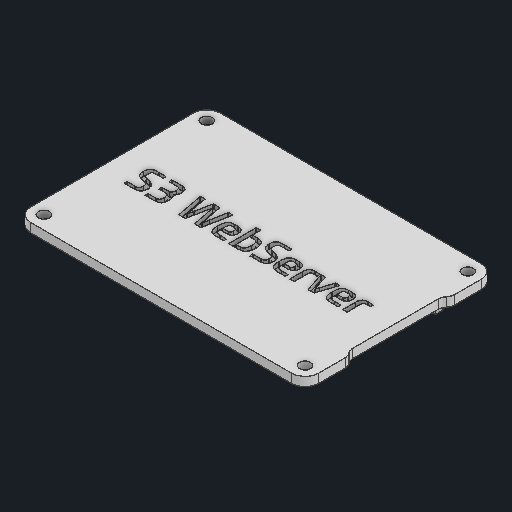
# Autodesk Inventor part: COVER
Saved by Autodesk Inventor 2027 (Build 310192000, 192)
## iProperties
Created: 2026-09-25
Part Number: COVER
Material: 일반
Document SubType Name: Modeling
Designer: work
Density: 1 g/cm^3
Appearance: 기본값
Author: work
Autodesk Inventor part; units mm, degrees
ref_plane "YZ Plane" through (0, 0, 0) normal (1, 0, 0) x (0, 1, 0)
ref_plane "XZ Plane" through (0, 0, 0) normal (0, 1, 0) x (-1, 0, 0)
ref_plane "XY Plane" through (0, 0, 0) normal (0, 0, 1) x (1, 0, 0)
sketch "스케치1" plane through (0, 0, 0) normal (0, 1, 0) x (-1, 0, 0)
  line L0 (0, 0) -> (58.5, 0)
  line L1 (58.5, 0) -> (58.5, -28.5)
  line L2 (58.5, -28.5) -> (0, -28.5)
  line L3 (0, -28.5) -> (0, 0)
  line L4 (-2, -30.5) -> (60.5, -30.5)
  line L5 (60.5, -30.5) -> (60.5, 2)
  line L6 (60.5, 2) -> (-2, 2)
  line L7 (-2, 2) -> (-2, -30.5)
  line L8 (0, -3.75) -> (-2, -3.75)
  line L9 (-2, -3.75) -> (-2, -24.75)
  line L10 (-2, -24.75) -> (0, -24.75)
  line L11 (0, -24.75) -> (0, -3.75)
  line L12 (58.5, -5.25) -> (60.5, -5.25)
  line L13 (60.5, -5.25) -> (60.5, -23.25)
  line L14 (60.5, -23.25) -> (58.5, -23.25)
  line L15 (58.5, -23.25) -> (58.5, -5.25)
  circle A0 centre (60.5, 0) radius 1.1
  line L16 (58.5, -14.25) -> (60.5, -14.25) construction
  circle A1 centre (60.5, 0) radius 2
  circle A2 centre (60.5, -28.5) radius 1.1
  circle A3 centre (60.5, -28.5) radius 2
  circle A4 centre (-2, 0) radius 1.1
  circle A5 centre (-2, 0) radius 2
  circle A6 centre (-2, -28.5) radius 1.1
  circle A7 centre (-2, -28.5) radius 2
  line L17 (58.5, 0) -> (48.5, 0)
  line L18 (48.5, 0) -> (48.5, -3)
  line L19 (48.5, -3) -> (58.5, -3)
  line L20 (58.5, -3) -> (58.5, 0)
  line L21 (48.5, -28.5) -> (48.5, -25.5)
  line L22 (48.5, -25.5) -> (58.5, -25.5)
  line L23 (29.25, -30.5) -> (29.25, 2) construction
  line L24 (10, 0) -> (10, -3)
  line L25 (10, -3) -> (0, -3)
  line L26 (10, -25.5) -> (0, -25.5)
  line L27 (10, -28.5) -> (10, -25.5)
  point P0 (0, -14.25)
  point P1 (-2, -14.25)
  point P2 (59.5, -23.25)
  point P3 (59.5, -5.25)
  point P4 (60.5, -2)
  point P5 (-2, -2)
  point P6 (-2, -26.5)
  point P7 (-2, -30.5)
  point P8 (60.5, -30.5)
  point P9 (60.5, -26.5)
  point P10 (10, -28.5)
  point P11 (0, -25.5)
  point P12 (48.5, -28.5)
  point P13 (48.5, 0)
  dimension "d0" = 58.5
  dimension "d1" = 28.5
  dimension "d2" = 2
  dimension "d3" = 21
  dimension "d4" = 18
  dimension "d5" = 2.2
  dimension "d6" = 2.2
  dimension "d7" = 10
  dimension "d8" = 3
  constraints: 56 end point, 13 symmetric about line, 12 midpoint, 10 parallel, 6 centre point, 5 horizontal, 5 perpendicular, 4 coincident, 2 horizontal alignment, 2 point on line, 13 other
  measures "d0" distance of L1.end L2.end
  measures "d1" distance of L0.end L1.end
  measures "d2" distance between parallel lines of L2 L4
  measures "d3" distance of L8.end L9.end
  measures "d4" distance of point (59.5, -23.25) point (59.5, -5.25)
  measures "d5" diameter of A0
  measures "d6" diameter of A4
  measures "d7" distance of L19.end L18.end
  measures "d8" distance of L18.end L17.end
extrude "돌출1" add sketch "스케치1" along normal blind 2 contours A5 L6 A1 L0 | L0 L24 L25 L3 | A5 L7 A4 | L3 L8 L7 A5 | L0 L18 L19 L1 L22 L21 L2 L27 L26 L3 L25 L24 | L0 L1 L19 L18 | L3 L10 L7 L8 | L5 A0 A1 | A4 L7 | A1 L5 L12 L1 | L3 A7 L7 L10 | L5 A0 | L26 L27 L2 L3 | A7 L7 A6 | L12 L5 L14 L1 | L2 A3 L4 A7 | A6 L7 | L14 L5 A3 L1 | A3 L5 A2 | L1 L2 L21 L22 | A2 L5 picked at (-0.3259, -0.2299) picked at (60.3517, -1.6833) picked at (-1.7714, 0.2867) picked at (60.136, -0.0442) picked at (-0.419, -27.9033) picked at (-1.5307, -28.8138) picked at (60.3517, -26.8167) picked at (60.136, -28.5442)
extrude "돌출2" add sketch "스케치1" against normal blind 3 contours L0 L24 L25 L3 | L0 L1 L19 L18 | L26 L27 L2 L3 | L1 L2 L21 L22
sketch "스케치2" plane through (0, -3, 0) normal (0, -1, 0) x (1, 0, 0)
  line L0 (0, -25.5) -> (0, -28.5) projected
  line L1 (0, -28.5) -> (-10, -28.5) projected
  line L2 (-10, -28.5) -> (-10, -25.5) projected
  line L3 (-10, -25.5) -> (0, -25.5) projected
  line L4 (-58.5, -28.5) -> (-58.5, -25.5) projected
  line L5 (-58.5, -25.5) -> (-48.5, -25.5) projected
  line L6 (-48.5, -25.5) -> (-48.5, -28.5) projected
  line L7 (-48.5, -28.5) -> (-58.5, -28.5) projected
  line L8 (0, 0) -> (0, -3) projected
  line L9 (0, -3) -> (-10, -3) projected
  line L10 (-10, -3) -> (-10, 0) projected
  line L11 (-10, 0) -> (0, 0) projected
  line L12 (-58.5, 0) -> (-48.5, 0) projected
  line L13 (-48.5, 0) -> (-48.5, -3) projected
  line L14 (-48.5, -3) -> (-58.5, -3) projected
  line L15 (-58.5, -3) -> (-58.5, 0) projected
  line L16 (-60.5, 2) -> (2, 2) projected
  line L17 (-60.5, -30.5) -> (-60.5, 2) projected
  line L18 (2, -30.5) -> (-60.5, -30.5) projected
  line L19 (2, 2) -> (2, -30.5) projected
  line L20 (-0.3, -28.2) -> (-58.3, -28.2)
  line L21 (-58.3, -28.2) -> (-58.3, -0.3)
  line L22 (-58.3, -0.3) -> (-0.3, -0.3)
  line L23 (-0.3, -0.3) -> (-0.3, -28.2)
  line L24 (-0.3, -28.2) -> (-58.3, -0.3) construction
  line L25 (-58.3, -28.2) -> (-0.3, -0.3) construction
  point P0 (-29.3, -14.25)
  point P1 (-0.3, -25.5)
  point P2 (-10, -28.2)
  point P3 (-48.5, -28.2)
  point P4 (-58.3, -25.5)
  point P5 (-58.3, -3)
  point P6 (-48.5, -0.3)
  point P7 (-10, -0.3)
  point P8 (-0.3, -3)
  dimension "d13" = 0.3
  dimension "d14" = 0.2
  dimension "d15" = 0.3
  dimension "d16" = 0.3
  constraints: 12 end point, 2 midpoint, 2 parallel, 1 horizontal, 1 perpendicular
  measures "d13" distance between parallel lines of L12 L22
  measures "d14" distance between parallel lines of L15 L21
  measures "d15" distance between parallel lines of L1 L20
  measures "d16" distance between parallel lines of L0 L23
extrude "돌출3" cut sketch "스케치2" against normal up to surface (3 mm away) contours L0 L1 L2 L20 L23 L3 | L23 L22 L10 L11 L8 L9 | L6 L7 L4 L5 L21 L20 | L22 L21 L14 L15 L12 L13
fillet "모깎기1" radius 1 4 edges at (-0.3, -1.5, -28.2) (-0.3, -1.5, -0.3) (-58.3, -1.5, -28.2) (-58.3, -1.5, -0.3)
extrude "돌출4" add sketch "스케치1" against normal blind 2 contours L12 L5 L14 L1
sketch "스케치3" plane through (0, -2, 0) normal (0, -1, 0) x (1, 0, 0)
  line L0 (-60.5, -30.5) -> (-60.5, 2) projected
  line L1 (-60.5, -14) -> (-58.5, -14.25) construction
  line L2 (-58.5, -23.25) -> (-58.5, -5.25) projected
  line L3 (-60.5, -22.95) -> (-58.5, -22.95)
  line L4 (-60.5, -23.25) -> (-58.5, -23.25) projected
  line L5 (-58.2969, -5.3254) -> (-56.3585, -5.8177)
  line L6 (-58.2231, -5.0346) -> (-58.5, -5.25)
  point P0 (0, 0)
  point P1 (-60, -26)
  point P2 (-60, -2)
  point P3 (-59.5, -22.95)
  point P4 (-60, -5)
  point P5 (-60, -5.3)
  point P6 (-58, -5.3)
  point P7 (-58.5, -22.95)
  point P8 (-60.5, -22.95)
  point P9 (-60.5, 2)
  dimension "d22" = 0.3
  constraints: 8 end point, 3 symmetric about line, 2 midpoint, 1 horizontal, 2 other
  measures "d22" distance from line of L4 point (-59.5, -22.95)
extrude "돌출5" cut sketch "스케치3" against normal blind 2
sketch "스케치4" plane through (0, 2, 0) normal (0, 1, 0) x (1, 0, 0)
  line L0 (-60.5, -2) -> (2, -2) projected
  line L1 (-14, -2) -> (-14, 30.5) construction
  line L2 (2, 30.5) -> (-60.5, 30.5) projected
  line L3 (2, -2) -> (2, 30.5) projected
  circle A0 centre (-14, 11.5) radius 0.5
  point P0 (0, 0)
  point P1 (2, 30)
  point P2 (-60, 30)
  point P3 (2, 2)
  point P4 (2, 26)
  dimension "d25" = 16
  dimension "d26" = 1
  dimension "d27" = 19
  constraints: 2 end point, 2 point on line, 1 centre point, 1 vertical, 2 other
  measures "d25" distance between parallel lines of L3 L1
  measures "d26" diameter of A0
  measures "d27" distance of L1.end A0.centre
sketch "스케치7" plane through (0, 0, 0) normal (0, -1, 0) x (1, 0, 0)
  line L0 (-60.5, -30.5) -> (-60.5, -22.95) projected
  line L1 (2, -30.5) -> (-60.5, -30.5) projected
  line L2 (2, 2) -> (2, -30.5) projected
  line L3 (-60.5, 2) -> (2, 2) projected
  line L4 (-60.5, -5.25) -> (-60.5, 2) projected
  line L5 (-58.5, -5.25) -> (-58.5, -22.95) projected
  line L6 (-60.5, -22.95) -> (-58.5, -22.95) projected
  line L7 (-10, -28.2) -> (-10, -25.5) projected
  line L8 (-10, -25.5) -> (-0.3, -25.5) projected
  line L9 (-0.3, -25.5) -> (-0.3, -27.2) projected
  arc A0 (-1.3, -28.2) -> (-0.3, -27.2) centre (-1.3, -27.2) ccw projected
  line L10 (-1.3, -28.2) -> (-10, -28.2) projected
  line L11 (-58.3, -25.5) -> (-48.5, -25.5) projected
  line L12 (-48.5, -25.5) -> (-48.5, -28.2) projected
  line L13 (-48.5, -28.2) -> (-57.3, -28.2) projected
  arc A1 (-58.3, -27.2) -> (-57.3, -28.2) centre (-57.3, -27.2) ccw projected
  line L14 (-58.3, -27.2) -> (-58.3, -25.5) projected
  line L15 (-0.3, -3) -> (-10, -3) projected
  line L16 (-10, -3) -> (-10, -0.3) projected
  line L17 (-10, -0.3) -> (-1.3, -0.3) projected
  arc A2 (-0.3, -1.3) -> (-1.3, -0.3) centre (-1.3, -1.3) ccw projected
  line L18 (-0.3, -1.3) -> (-0.3, -3) projected
  line L19 (-48.5, -0.3) -> (-48.5, -3) projected
  line L20 (-48.5, -3) -> (-58.3, -3) projected
  line L21 (-58.3, -3) -> (-58.3, -1.3) projected
  arc A3 (-57.3, -0.3) -> (-58.3, -1.3) centre (-57.3, -1.3) ccw projected
  line L22 (-57.3, -0.3) -> (-48.5, -0.3) projected
  line L23 (-10, -0.3) -> (-48.5, -0.3)
  line L24 (-48.5, -0.3) -> (-48.5, -3)
  line L25 (-48.5, -3) -> (-10, -3)
  line L26 (-10, -3) -> (-10, -0.3)
  line L27 (-10, -25.5) -> (-48.5, -25.5)
  line L28 (-48.5, -25.5) -> (-48.5, -28.2)
  line L29 (-48.5, -28.2) -> (-10, -28.2)
  line L30 (-10, -28.2) -> (-10, -25.5)
  line L31 (-60.5, -5.25) -> (-58.5, -5.25) projected
  point P0 (0, 0)
  constraints: 16 end point, 4 parallel, 2 horizontal, 2 perpendicular
extrude "돌출7" add sketch "스케치7" along normal up to surface (3 mm away) contours L29 L12 L27 L7 | L25 L19 L23 L16
fillet "모깎기4" radius 2 2 edges at (-29.3, 0, -3) (-29.3, 0, -25.5)
sketch "스케치8" plane through (0, 0, 0) normal (0, -1, 0) x (1, 0, 0)
  line L0 (2, 2) -> (2, -30.5) projected
  line L1 (2, -14.25) -> (-60.5, -14.25) construction
  line L2 (-60.5, -30.5) -> (-60.5, 2) projected
  circle A0 centre (0, -32.5) radius 1.25
  line L3 (2, -30.5) -> (-60.5, -30.5) projected
  circle A1 centre (-58.5, -32.5) radius 1.25
  line L4 (0, -32.5) -> (-58.5, -32.5) construction
  line L5 (0, -30.5) -> (-58.5, -30.5)
  line L6 (-58.5, -34.5) -> (0, -34.5)
  arc A2 (0, -34.5) -> (0, -30.5) centre (0, -32.5) ccw
  arc A3 (-58.5, -30.5) -> (-58.5, -34.5) centre (-58.5, -32.5) ccw
  line L7 (-60.5, -30.5) -> (-60.5, -32.5)
  line L8 (2, -32.5) -> (2, -30.5)
  circle A4 centre (0, 4) radius 1.25
  circle A5 centre (-58.5, 4) radius 1.25
  line L9 (0, 4) -> (-58.5, 4) construction
  line L10 (-58.5, 6) -> (0, 6)
  arc A6 (0, 2) -> (0, 6) centre (0, 4) ccw
  arc A7 (-58.5, 6) -> (-58.5, 2) centre (-58.5, 4) ccw
  line L11 (-60.5, 2) -> (-60.5, 4)
  line L12 (2, 4) -> (2, 2)
  point P0 (0, 0)
  point P1 (-29.25, -32.5)
  point P2 (-58.5, -30.5)
  point P3 (0, -30.5)
  dimension "d46" = 2.5
  dimension "d47" = 2
  dimension "d48" = 2
  dimension "d49" = 2.5
  dimension "d50" = 2
  dimension "d51" = 2
  constraints: 24 end point, 10 point on circle, 9 symmetric about line, 8 centre point, 5 tangent, 3 midpoint, 2 coincident, 1 parallel, 4 other
  measures "d46" diameter of A0
  measures "d47" distance from line of L3 L4.start
  measures "d48" horizontal distance of L0.end L4.start
  measures "d49" diameter of A1
  measures "d50" horizontal distance of L2.start A1.centre
  measures "d51" horizontal distance of A1.centre L2.start
extrude "돌출8" add sketch "스케치8" against normal up to surface (2 mm away)
fillet "모깎기5" radius 2 1 edges at (-58.5, 0, -14.1)
sketch "스케치9" plane through (0, 2, 0) normal (0, 1, 0) x (1, 0, 0)
  circle A0 centre (-58.5, -4) radius 0.95
  circle A1 centre (0, -4) radius 0.95
  line L0 (-58.5, 0) -> (-58.5, 5.25)
  line L1 (-58.5, 5.25) -> (-61.5, 5.25)
  line L2 (-61.5, 5.25) -> (-61.5, -4)
  arc A2 (-61.5, -4) -> (-58.5, -7) centre (-58.5, -4) ccw
  line L3 (-58.5, -7) -> (0, -7)
  arc A3 (0, -7) -> (3, -4) centre (0, -4) ccw
  line L4 (3, -4) -> (3, 3.75)
  line L5 (3, 3.75) -> (0, 3.75)
  line L6 (0, 3.75) -> (0, 0)
  line L7 (0, 0) -> (-58.5, 0)
  circle A4 centre (0, 32.5) radius 0.95
  circle A5 centre (-58.5, 32.5) radius 0.95
  line L8 (-61.5, 23.25) -> (-58.5, 23.25)
  line L9 (-58.5, 23.25) -> (-58.5, 28.5)
  line L10 (-58.5, 28.5) -> (0, 28.5)
  line L11 (0, 28.5) -> (0, 24.75)
  line L12 (0, 24.75) -> (3, 24.75)
  line L13 (3, 24.75) -> (3, 32.5)
  arc A6 (3, 32.5) -> (0, 35.5) centre (0, 32.5) ccw
  line L14 (0, 35.5) -> (-58.5, 35.5)
  arc A7 (-58.5, 35.5) -> (-61.5, 32.5) centre (-58.5, 32.5) ccw
  line L15 (-61.5, 32.5) -> (-61.5, 23.25)
  line L16 (2, 24.75) -> (2, 3.75) construction
  line L17 (2, 3.75) -> (3, 3.75) construction
  line L18 (3, 3.75) -> (3, -4) construction
  arc A8 (0, -7) -> (3, -4) centre (0, -4) ccw construction
  line L19 (0, -7) -> (-58.5, -7) construction
  arc A9 (-61.5, -4) -> (-58.5, -7) centre (-58.5, -4) ccw construction
  line L20 (-61.5, -4) -> (-61.5, 5.25) construction
  line L21 (-61.5, 5.25) -> (-60.5, 5.25) construction
  line L22 (-60.5, 23.25) -> (-60.5, 5.25) construction
  line L23 (-60.5, 23.25) -> (-61.5, 23.25) construction
  line L24 (-61.5, 23.25) -> (-61.5, 32.5) construction
  arc A10 (-58.5, 35.5) -> (-61.5, 32.5) centre (-58.5, 32.5) ccw construction
  line L25 (-58.5, 35.5) -> (0, 35.5) construction
  arc A11 (3, 32.5) -> (0, 35.5) centre (0, 32.5) ccw construction
  line L26 (3, 32.5) -> (3, 24.75) construction
  line L27 (3, 24.75) -> (2, 24.75) construction
  circle A12 centre (-58.5, 32.5) radius 1.25 projected
  circle A13 centre (0, 32.5) radius 1.25 projected
  circle A14 centre (-58.5, -4) radius 1.25 projected
  circle A15 centre (0, -4) radius 1.25 projected
  line L28 (2, 32.5) -> (2, -4) projected
  arc A16 (2, 32.5) -> (0, 34.5) centre (0, 32.5) ccw projected
  line L29 (-58.5, 34.5) -> (0, 34.5) projected
  arc A17 (-58.5, 34.5) -> (-60.5, 32.5) centre (-58.5, 32.5) ccw projected
  line L30 (-60.5, -4) -> (-60.5, 32.5) projected
  arc A18 (-60.5, -4) -> (-58.5, -6) centre (-58.5, -4) ccw projected
  line L31 (0, -6) -> (-58.5, -6) projected
  arc A19 (0, -6) -> (2, -4) centre (0, -4) ccw projected
  line L32 (-61.5, 5.25) -> (-61.5, 23.25)
  line L33 (3, 24.75) -> (3, 3.75)
  point P0 (0, 0)
  point P1 (2, 3.75)
  point P2 (2, 24.75)
  constraints: 60 end point, 16 point on circle, 12 centre point, 1 parallel, 1 vertical
extrude "돌출9" add sketch "스케치9" against normal up to surface (2 mm away) contours L7 L6 L5 L28 A19 L31 A18 L30 L1 L0 | L0 L1 L30 L8 L9 L10 L11 L12 L28 L5 L6 L7 | L30 A18 L31 A19 L28 L5 L4 A3 L3 A2 L2 L1 | L1 L32 L8 L30 | L30 A17 L29 A16 L28 L12 L11 L10 L9 L8 | L8 L15 A7 L14 A6 L13 L12 L28 A16 L29 A17 L30
fillet "모깎기6" radius 2 4 edges at (2, 1, -3.75) (2, 1, -24.75) (3, 1, -24.75) (3, 1, -3.75)
sketch "스케치11" plane through (0, 2, 0) normal (0, 1, 0) x (1, 0, 0)
  line L0 (-56.1428, 17.2765) -> (30.9007, 17.2765) construction
  line L1 (30.9007, 17.2765) -> (30.9007, -13.3116) construction
  line L2 (30.9007, -13.3116) -> (-56.1428, -13.3116) construction
  line L3 (-56.1428, -13.3116) -> (-56.1428, 17.2765) construction
  spline S0 degree 2 poles (-53.8297, 16.4272) (-54.1294, 16.4272) (-54.4991, 16.3523) (-54.699, 16.1575) (-54.7689, 15.8127) (-54.7689, 15.543) knots 0 0 0 1 2 3 4 4 4
  spline S1 degree 2 poles (-54.7689, 15.543) (-54.7689, 15.3381) (-54.7389, 15.0484) (-54.629, 14.8386) (-54.4142, 14.6937) (-54.2294, 14.6437) knots 0 0 0 1 2 3 4 4 4
  line L4 (-54.2294, 14.6437) -> (-53.0603, 14.324)
  spline S2 degree 2 poles (-53.0603, 14.324) (-52.7206, 14.2291) (-52.266, 13.9393) (-51.9862, 13.5297) (-51.8713, 13.0051) (-51.8713, 12.6704) knots 0 0 0 1 2 3 4 4 4
  spline S3 degree 2 poles (-51.8713, 12.6704) (-51.8713, 12.1658) (-52.1011, 11.5413) (-52.5907, 11.2066) (-53.3451, 11.0917) (-53.8747, 11.0917) knots 0 0 0 1 2 3 4 4 4
  line L5 (-53.8747, 11.0917) -> (-55.5982, 11.0917)
  spline S4 degree 2 poles (-55.5982, 11.0917) (-55.6831, 11.0917) (-55.6831, 11.1666) knots 0 0 0 1 1 1
  line L6 (-55.6831, 11.1666) -> (-55.6831, 11.6812)
  spline S5 degree 2 poles (-55.6831, 11.6812) (-55.6831, 11.7311) (-55.6332, 11.7561) (-55.5982, 11.7561) knots 0 0 0 1 2 2 2
  line L7 (-55.5982, 11.7561) -> (-53.8597, 11.7561)
  spline S6 degree 2 poles (-53.8597, 11.7561) (-53.5399, 11.7561) (-53.1603, 11.866) (-52.9754, 12.0859) (-52.9205, 12.4356) (-52.9205, 12.6804) knots 0 0 0 1 2 3 4 4 4
  spline S7 degree 2 poles (-52.9205, 12.6804) (-52.9205, 12.8952) (-52.9504, 13.1899) (-53.0603, 13.3848) (-53.2652, 13.5147) (-53.445, 13.5596) knots 0 0 0 1 2 3 4 4 4
  line L8 (-53.445, 13.5596) -> (-54.629, 13.8943)
  spline S8 degree 2 poles (-54.629, 13.8943) (-55.2885, 14.0792) (-55.803, 14.8935) (-55.803, 15.563) knots 0 0 0 1 2 2 2
  spline S9 degree 2 poles (-55.803, 15.563) (-55.803, 16.0725) (-55.5732, 16.682) (-55.0936, 16.9968) (-54.3692, 17.0917) (-53.8647, 17.0917) knots 0 0 0 1 2 3 4 4 4
  line L9 (-53.8647, 17.0917) -> (-52.306, 17.0917)
  spline S10 degree 2 poles (-52.306, 17.0917) (-52.221, 17.0917) (-52.221, 17.0167) knots 0 0 0 1 1 1
  line L10 (-52.221, 17.0167) -> (-52.221, 16.5022)
  spline S11 degree 2 poles (-52.221, 16.5022) (-52.221, 16.4522) (-52.271, 16.4272) (-52.306, 16.4272) knots 0 0 0 1 2 2 2
  line L11 (-52.306, 16.4272) -> (-53.8297, 16.4272)
  spline S12 degree 2 poles (-50.9271, 11.0917) (-51.012, 11.0917) (-51.012, 11.1666) knots 0 0 0 1 1 1
  line L12 (-51.012, 11.1666) -> (-51.012, 11.6812)
  spline S13 degree 2 poles (-51.012, 11.6812) (-51.012, 11.7311) (-50.9621, 11.7561) (-50.9271, 11.7561) knots 0 0 0 1 2 2 2
  line L13 (-50.9271, 11.7561) -> (-49.1336, 11.7561)
  spline S14 degree 2 poles (-49.1336, 11.7561) (-48.9438, 11.7561) (-48.644, 11.8411) (-48.4492, 12.0709) (-48.3493, 12.4805) (-48.3493, 12.8053) knots 0 0 0 1 2 3 4 4 4
  spline S15 degree 2 poles (-48.3493, 12.8053) (-48.3493, 13.13) (-48.4492, 13.5446) (-48.644, 13.7744) (-48.9438, 13.8694) (-49.1386, 13.8694) knots 0 0 0 1 2 3 4 4 4
  line L14 (-49.1386, 13.8694) -> (-50.6274, 13.8694)
  spline S16 degree 2 poles (-50.6274, 13.8694) (-50.6623, 13.8694) (-50.7123, 13.8943) (-50.7123, 13.9443) knots 0 0 0 1 2 2 2
  line L15 (-50.7123, 13.9443) -> (-50.7123, 14.4589)
  spline S17 degree 2 poles (-50.7123, 14.4589) (-50.7123, 14.5338) (-50.6274, 14.5338) knots 0 0 0 1 1 1
  line L16 (-50.6274, 14.5338) -> (-48.9737, 14.5338)
  spline S18 degree 2 poles (-48.9737, 14.5338) (-48.629, 14.5338) (-48.4042, 15.0284) (-48.4042, 15.543) knots 0 0 0 1 2 2 2
  spline S19 degree 2 poles (-48.4042, 15.543) (-48.4042, 15.9826) (-48.644, 16.4272) (-49.0387, 16.4272) knots 0 0 0 1 2 2 2
  line L17 (-49.0387, 16.4272) -> (-50.8472, 16.4272)
  spline S20 degree 2 poles (-50.8472, 16.4272) (-50.8871, 16.4272) (-50.9321, 16.4522) (-50.9321, 16.5022) knots 0 0 0 1 2 2 2
  line L18 (-50.9321, 16.5022) -> (-50.9321, 17.0167)
  spline S21 degree 2 poles (-50.9321, 17.0167) (-50.9321, 17.0917) (-50.8472, 17.0917) knots 0 0 0 1 1 1
  line L19 (-50.8472, 17.0917) -> (-48.5641, 17.0917)
  spline S22 degree 2 poles (-48.5641, 17.0917) (-48.2344, 17.0917) (-47.7697, 16.8819) (-47.495, 16.4822) (-47.3701, 15.9027) (-47.3701, 15.543) knots 0 0 0 1 2 3 4 4 4
  spline S23 degree 2 poles (-47.3701, 15.543) (-47.3701, 15.1933) (-47.5849, 14.5238) (-47.8347, 14.309) knots 0 0 0 1 2 2 2
  spline S24 degree 2 poles (-47.8347, 14.309) (-47.3151, 13.9293) (-47.3151, 12.8053) knots 0 0 0 1 1 1
  spline S25 degree 2 poles (-47.3151, 12.8053) (-47.3151, 11.896) (-47.9496, 11.0917) (-48.629, 11.0917) knots 0 0 0 1 2 2 2
  line L20 (-48.629, 11.0917) -> (-50.9271, 11.0917)
  line L21 (-39.1619, 12.1558) -> (-38.9471, 13.5247)
  line L22 (-38.9471, 13.5247) -> (-38.3076, 17.0367)
  spline S26 degree 2 poles (-38.3076, 17.0367) (-38.2976, 17.0917) (-38.2277, 17.0917) knots 0 0 0 1 1 1
  line L23 (-38.2277, 17.0917) -> (-37.3185, 17.0917)
  spline S27 degree 2 poles (-37.3185, 17.0917) (-37.2585, 17.0917) (-37.2735, 17.0217) knots 0 0 0 1 1 1
  line L24 (-37.2735, 17.0217) -> (-38.3676, 11.2865)
  spline S28 degree 2 poles (-38.3676, 11.2865) (-38.3976, 11.1516) (-38.5075, 11.0917) (-38.6374, 11.0917) knots 0 0 0 1 2 2 2
  line L25 (-38.6374, 11.0917) -> (-39.6415, 11.0917)
  spline S29 degree 2 poles (-39.6415, 11.0917) (-39.7714, 11.0917) (-39.8813, 11.1516) (-39.9113, 11.2865) knots 0 0 0 1 2 2 2
  line L26 (-39.9113, 11.2865) -> (-40.8755, 16.1125)
  line L27 (-40.8755, 16.1125) -> (-40.9354, 16.1125)
  line L28 (-40.9354, 16.1125) -> (-41.8996, 11.2865)
  spline S30 degree 2 poles (-41.8996, 11.2865) (-41.9346, 11.1516) (-42.0395, 11.0917) (-42.1694, 11.0917) knots 0 0 0 1 2 2 2
  line L29 (-42.1694, 11.0917) -> (-43.1736, 11.0917)
  spline S31 degree 2 poles (-43.1736, 11.0917) (-43.3035, 11.0917) (-43.4134, 11.1516) (-43.4433, 11.2865) knots 0 0 0 1 2 2 2
  line L30 (-43.4433, 11.2865) -> (-44.5374, 17.0217)
  spline S32 degree 2 poles (-44.5374, 17.0217) (-44.5524, 17.0917) (-44.4925, 17.0917) knots 0 0 0 1 1 1
  line L31 (-44.4925, 17.0917) -> (-43.5832, 17.0917)
  spline S33 degree 2 poles (-43.5832, 17.0917) (-43.5133, 17.0917) (-43.5033, 17.0367) knots 0 0 0 1 1 1
  line L32 (-43.5033, 17.0367) -> (-42.8638, 13.5247)
  line L33 (-42.8638, 13.5247) -> (-42.649, 12.1558)
  line L34 (-42.649, 12.1558) -> (-42.5891, 12.1558)
  line L35 (-42.5891, 12.1558) -> (-42.3493, 13.4947)
  line L36 (-42.3493, 13.4947) -> (-41.6598, 16.9518)
  spline S34 degree 2 poles (-41.6598, 16.9518) (-41.6448, 17.0467) (-41.5599, 17.0917) (-41.475, 17.0917) knots 0 0 0 1 2 2 2
  line L37 (-41.475, 17.0917) -> (-40.3409, 17.0917)
  spline S35 degree 2 poles (-40.3409, 17.0917) (-40.256, 17.0917) (-40.1811, 17.0517) (-40.1561, 16.9618) knots 0 0 0 1 2 2 2
  line L38 (-40.1561, 16.9618) -> (-39.4617, 13.4947)
  line L39 (-39.4617, 13.4947) -> (-39.2269, 12.1558)
  line L40 (-39.2269, 12.1558) -> (-39.1619, 12.1558)
  spline S36 degree 2 poles (-33.3817, 11.7311) (-33.3118, 11.7311) (-33.3118, 11.6612) knots 0 0 0 1 1 1
  line L41 (-33.3118, 11.6612) -> (-33.3118, 11.1616)
  spline S37 degree 2 poles (-33.3118, 11.1616) (-33.3118, 11.0917) (-33.3817, 11.0917) knots 0 0 0 1 1 1
  line L42 (-33.3817, 11.0917) -> (-34.9005, 11.0917)
  spline S38 degree 2 poles (-34.9005, 11.0917) (-35.455, 11.0917) (-36.2044, 11.3015) (-36.669, 11.8011) (-36.8638, 12.6254) (-36.8638, 13.2449) knots 0 0 0 1 2 3 4 4 4
  spline S39 degree 2 poles (-36.8638, 13.2449) (-36.8638, 13.8444) (-36.7339, 14.6937) (-36.3842, 15.2282) (-35.7847, 15.473) (-35.3201, 15.473) knots 0 0 0 1 2 3 4 4 4
  line L43 (-35.3201, 15.473) -> (-34.4808, 15.473)
  spline S40 degree 2 poles (-34.4808, 15.473) (-33.7165, 15.473) (-33.102, 14.7936) (-33.102, 14.1142) knots 0 0 0 1 2 2 2
  spline S41 degree 2 poles (-33.102, 14.1142) (-33.102, 13.4247) (-33.7464, 12.7753) (-34.4708, 12.7753) knots 0 0 0 1 2 2 2
  line L44 (-34.4708, 12.7753) -> (-35.8497, 12.7753)
  spline S42 degree 2 poles (-35.8497, 12.7753) (-35.8247, 12.4655) (-35.7098, 12.0659) (-35.48, 11.8261) (-35.0953, 11.7311) (-34.8105, 11.7311) knots 0 0 0 1 2 3 4 4 4
  line L45 (-34.8105, 11.7311) -> (-33.3817, 11.7311)
  spline S43 degree 2 poles (-34.5558, 13.4147) (-34.286, 13.4147) (-34.1111, 13.7545) (-34.1111, 14.1142) knots 0 0 0 1 2 2 2
  spline S44 degree 2 poles (-34.1111, 14.1142) (-34.1111, 14.4889) (-34.286, 14.8336) (-34.5558, 14.8336) knots 0 0 0 1 2 2 2
  line L46 (-34.5558, 14.8336) -> (-35.2352, 14.8336)
  spline S45 degree 2 poles (-35.2352, 14.8336) (-35.435, 14.8336) (-35.6748, 14.7037) (-35.8147, 14.3789) (-35.8597, 13.8294) (-35.8597, 13.4147) knots 0 0 0 1 2 3 4 4 4
  line L47 (-35.8597, 13.4147) -> (-34.5558, 13.4147)
  spline S46 degree 2 poles (-30.1394, 15.4131) (-29.6848, 15.4131) (-28.9804, 15.1833) (-28.5108, 14.6737) (-28.266, 13.8444) (-28.266, 13.2549) knots 0 0 0 1 2 3 4 4 4
  spline S47 degree 2 poles (-28.266, 13.2549) (-28.266, 12.6604) (-28.5108, 11.8311) (-28.9804, 11.3215) (-29.6848, 11.0917) (-30.1394, 11.0917) knots 0 0 0 1 2 3 4 4 4
  line L48 (-30.1394, 11.0917) -> (-32.0678, 11.0917)
  spline S48 degree 2 poles (-32.0678, 11.0917) (-32.1528, 11.0917) (-32.2127, 11.1616) (-32.2127, 11.2615) knots 0 0 0 1 2 2 2
  line L49 (-32.2127, 11.2615) -> (-32.2127, 17.2066)
  spline S49 degree 2 poles (-32.2127, 17.2066) (-32.2127, 17.2765) (-32.1528, 17.2765) knots 0 0 0 1 1 1
  line L50 (-32.1528, 17.2765) -> (-31.2785, 17.2765)
  spline S50 degree 2 poles (-31.2785, 17.2765) (-31.2185, 17.2765) (-31.2185, 17.2066) knots 0 0 0 1 1 1
  line L51 (-31.2185, 17.2066) -> (-31.2185, 15.4131)
  line L52 (-31.2185, 15.4131) -> (-30.1394, 15.4131)
  spline S51 degree 2 poles (-30.1394, 11.7311) (-29.9096, 11.7311) (-29.5849, 11.886) (-29.3751, 12.2507) (-29.2752, 12.8252) (-29.2752, 13.2549) knots 0 0 0 1 2 3 4 4 4
  spline S52 degree 2 poles (-29.2752, 13.2549) (-29.2752, 13.6795) (-29.3751, 14.254) (-29.5849, 14.6187) (-29.9096, 14.7736) (-30.1394, 14.7736) knots 0 0 0 1 2 3 4 4 4
  line L53 (-30.1394, 14.7736) -> (-31.2185, 14.7736)
  line L54 (-31.2185, 14.7736) -> (-31.2185, 11.7311)
  line L55 (-31.2185, 11.7311) -> (-30.1394, 11.7311)
  spline S53 degree 2 poles (-25.6432, 16.4272) (-25.9429, 16.4272) (-26.3126, 16.3523) (-26.5125, 16.1575) (-26.5824, 15.8127) (-26.5824, 15.543) knots 0 0 0 1 2 3 4 4 4
  spline S54 degree 2 poles (-26.5824, 15.543) (-26.5824, 15.3381) (-26.5524, 15.0484) (-26.4425, 14.8386) (-26.2277, 14.6937) (-26.0428, 14.6437) knots 0 0 0 1 2 3 4 4 4
  line L56 (-26.0428, 14.6437) -> (-24.8738, 14.324)
  spline S55 degree 2 poles (-24.8738, 14.324) (-24.5341, 14.2291) (-24.0795, 13.9393) (-23.7997, 13.5297) (-23.6848, 13.0051) (-23.6848, 12.6704) knots 0 0 0 1 2 3 4 4 4
  spline S56 degree 2 poles (-23.6848, 12.6704) (-23.6848, 12.1658) (-23.9146, 11.5413) (-24.4042, 11.2066) (-25.1586, 11.0917) (-25.6881, 11.0917) knots 0 0 0 1 2 3 4 4 4
  line L57 (-25.6881, 11.0917) -> (-27.4117, 11.0917)
  spline S57 degree 2 poles (-27.4117, 11.0917) (-27.4966, 11.0917) (-27.4966, 11.1666) knots 0 0 0 1 1 1
  line L58 (-27.4966, 11.1666) -> (-27.4966, 11.6812)
  spline S58 degree 2 poles (-27.4966, 11.6812) (-27.4966, 11.7311) (-27.4467, 11.7561) (-27.4117, 11.7561) knots 0 0 0 1 2 2 2
  line L59 (-27.4117, 11.7561) -> (-25.6732, 11.7561)
  spline S59 degree 2 poles (-25.6732, 11.7561) (-25.3534, 11.7561) (-24.9737, 11.866) (-24.7889, 12.0859) (-24.7339, 12.4356) (-24.7339, 12.6804) knots 0 0 0 1 2 3 4 4 4
  spline S60 degree 2 poles (-24.7339, 12.6804) (-24.7339, 12.8952) (-24.7639, 13.1899) (-24.8738, 13.3848) (-25.0787, 13.5147) (-25.2585, 13.5596) knots 0 0 0 1 2 3 4 4 4
  line L60 (-25.2585, 13.5596) -> (-26.4425, 13.8943)
  spline S61 degree 2 poles (-26.4425, 13.8943) (-27.102, 14.0792) (-27.6165, 14.8935) (-27.6165, 15.563) knots 0 0 0 1 2 2 2
  spline S62 degree 2 poles (-27.6165, 15.563) (-27.6165, 16.0725) (-27.3867, 16.682) (-26.9071, 16.9968) (-26.1827, 17.0917) (-25.6782, 17.0917) knots 0 0 0 1 2 3 4 4 4
  line L61 (-25.6782, 17.0917) -> (-24.1195, 17.0917)
  spline S63 degree 2 poles (-24.1195, 17.0917) (-24.0345, 17.0917) (-24.0345, 17.0167) knots 0 0 0 1 1 1
  line L62 (-24.0345, 17.0167) -> (-24.0345, 16.5022)
  spline S64 degree 2 poles (-24.0345, 16.5022) (-24.0345, 16.4522) (-24.0845, 16.4272) (-24.1195, 16.4272) knots 0 0 0 1 2 2 2
  line L63 (-24.1195, 16.4272) -> (-25.6432, 16.4272)
  spline S65 degree 2 poles (-19.6232, 11.7311) (-19.5533, 11.7311) (-19.5533, 11.6612) knots 0 0 0 1 1 1
  line L64 (-19.5533, 11.6612) -> (-19.5533, 11.1616)
  spline S66 degree 2 poles (-19.5533, 11.1616) (-19.5533, 11.0917) (-19.6232, 11.0917) knots 0 0 0 1 1 1
  line L65 (-19.6232, 11.0917) -> (-21.1419, 11.0917)
  spline S67 degree 2 poles (-21.1419, 11.0917) (-21.6965, 11.0917) (-22.4458, 11.3015) (-22.9105, 11.8011) (-23.1053, 12.6254) (-23.1053, 13.2449) knots 0 0 0 1 2 3 4 4 4
  spline S68 degree 2 poles (-23.1053, 13.2449) (-23.1053, 13.8444) (-22.9754, 14.6937) (-22.6257, 15.2282) (-22.0262, 15.473) (-21.5616, 15.473) knots 0 0 0 1 2 3 4 4 4
  line L66 (-21.5616, 15.473) -> (-20.7223, 15.473)
  spline S69 degree 2 poles (-20.7223, 15.473) (-19.9579, 15.473) (-19.3434, 14.7936) (-19.3434, 14.1142) knots 0 0 0 1 2 2 2
  spline S70 degree 2 poles (-19.3434, 14.1142) (-19.3434, 13.4247) (-19.9879, 12.7753) (-20.7123, 12.7753) knots 0 0 0 1 2 2 2
  line L67 (-20.7123, 12.7753) -> (-22.0911, 12.7753)
  spline S71 degree 2 poles (-22.0911, 12.7753) (-22.0662, 12.4655) (-21.9513, 12.0659) (-21.7214, 11.8261) (-21.3368, 11.7311) (-21.052, 11.7311) knots 0 0 0 1 2 3 4 4 4
  line L68 (-21.052, 11.7311) -> (-19.6232, 11.7311)
  spline S72 degree 2 poles (-20.7972, 13.4147) (-20.5274, 13.4147) (-20.3526, 13.7545) (-20.3526, 14.1142) knots 0 0 0 1 2 2 2
  spline S73 degree 2 poles (-20.3526, 14.1142) (-20.3526, 14.4889) (-20.5274, 14.8336) (-20.7972, 14.8336) knots 0 0 0 1 2 2 2
  line L69 (-20.7972, 14.8336) -> (-21.4767, 14.8336)
  spline S74 degree 2 poles (-21.4767, 14.8336) (-21.6765, 14.8336) (-21.9163, 14.7037) (-22.0562, 14.3789) (-22.1011, 13.8294) (-22.1011, 13.4147) knots 0 0 0 1 2 3 4 4 4
  line L70 (-22.1011, 13.4147) -> (-20.7972, 13.4147)
  spline S75 degree 2 poles (-16.0562, 15.4131) (-15.9862, 15.4131) (-15.9862, 15.3431) knots 0 0 0 1 1 1
  line L71 (-15.9862, 15.3431) -> (-15.9862, 14.8036)
  spline S76 degree 2 poles (-15.9862, 14.8036) (-15.9862, 14.7336) (-16.0562, 14.7336) knots 0 0 0 1 1 1
  line L72 (-16.0562, 14.7336) -> (-16.8905, 14.7336)
  spline S77 degree 2 poles (-16.8905, 14.7336) (-17.0453, 14.7336) (-17.2702, 14.6887) (-17.425, 14.5238) (-17.5, 14.2091) (-17.5, 13.9443) knots 0 0 0 1 2 3 4 4 4
  line L73 (-17.5, 13.9443) -> (-17.5, 11.1616)
  spline S78 degree 2 poles (-17.5, 11.1616) (-17.5, 11.0917) (-17.5599, 11.0917) knots 0 0 0 1 1 1
  line L74 (-17.5599, 11.0917) -> (-18.4342, 11.0917)
  spline S79 degree 2 poles (-18.4342, 11.0917) (-18.4941, 11.0917) (-18.4941, 11.1616) knots 0 0 0 1 1 1
  line L75 (-18.4941, 11.1616) -> (-18.4941, 13.9793)
  spline S80 degree 2 poles (-18.4941, 13.9793) (-18.4941, 14.4239) (-18.2943, 14.9884) (-17.9396, 15.2982) (-17.46, 15.4131) (-17.1852, 15.4131) knots 0 0 0 1 2 3 4 4 4
  line L76 (-17.1852, 15.4131) -> (-16.0562, 15.4131)
  spline S81 degree 2 poles (-14.2377, 11.0917) (-14.3376, 11.0917) (-14.4325, 11.1616) (-14.4675, 11.2615) knots 0 0 0 1 2 2 2
  line L77 (-14.4675, 11.2615) -> (-15.8014, 15.3581)
  spline S82 degree 2 poles (-15.8014, 15.3581) (-15.8164, 15.4131) (-15.7664, 15.4131) knots 0 0 0 1 1 1
  line L78 (-15.7664, 15.4131) -> (-14.9321, 15.4131)
  spline S83 degree 2 poles (-14.9321, 15.4131) (-14.8522, 15.4131) (-14.8322, 15.3581) knots 0 0 0 1 1 1
  line L79 (-14.8322, 15.3581) -> (-13.9829, 12.6354)
  line L80 (-13.9829, 12.6354) -> (-13.7531, 11.901)
  line L81 (-13.7531, 11.901) -> (-13.6981, 11.901)
  line L82 (-13.6981, 11.901) -> (-13.4683, 12.6354)
  line L83 (-13.4683, 12.6354) -> (-12.619, 15.3581)
  spline S84 degree 2 poles (-12.619, 15.3581) (-12.5941, 15.4131) (-12.5191, 15.4131) knots 0 0 0 1 1 1
  line L84 (-12.5191, 15.4131) -> (-11.6848, 15.4131)
  spline S85 degree 2 poles (-11.6848, 15.4131) (-11.6299, 15.4131) (-11.6448, 15.3581) knots 0 0 0 1 1 1
  line L85 (-11.6448, 15.3581) -> (-12.9787, 11.2615)
  spline S86 degree 2 poles (-12.9787, 11.2615) (-13.0187, 11.1616) (-13.1136, 11.0917) (-13.2135, 11.0917) knots 0 0 0 1 2 2 2
  line L86 (-13.2135, 11.0917) -> (-14.2377, 11.0917)
  spline S87 degree 2 poles (-7.7581, 11.7311) (-7.6881, 11.7311) (-7.6881, 11.6612) knots 0 0 0 1 1 1
  line L87 (-7.6881, 11.6612) -> (-7.6881, 11.1616)
  spline S88 degree 2 poles (-7.6881, 11.1616) (-7.6881, 11.0917) (-7.7581, 11.0917) knots 0 0 0 1 1 1
  line L88 (-7.7581, 11.0917) -> (-9.2768, 11.0917)
  spline S89 degree 2 poles (-9.2768, 11.0917) (-9.8314, 11.0917) (-10.5807, 11.3015) (-11.0453, 11.8011) (-11.2402, 12.6254) (-11.2402, 13.2449) knots 0 0 0 1 2 3 4 4 4
  spline S90 degree 2 poles (-11.2402, 13.2449) (-11.2402, 13.8444) (-11.1103, 14.6937) (-10.7606, 15.2282) (-10.1611, 15.473) (-9.6965, 15.473) knots 0 0 0 1 2 3 4 4 4
  line L89 (-9.6965, 15.473) -> (-8.8572, 15.473)
  spline S91 degree 2 poles (-8.8572, 15.473) (-8.0928, 15.473) (-7.4783, 14.7936) (-7.4783, 14.1142) knots 0 0 0 1 2 2 2
  spline S92 degree 2 poles (-7.4783, 14.1142) (-7.4783, 13.4247) (-8.1228, 12.7753) (-8.8472, 12.7753) knots 0 0 0 1 2 2 2
  line L90 (-8.8472, 12.7753) -> (-10.226, 12.7753)
  spline S93 degree 2 poles (-10.226, 12.7753) (-10.201, 12.4655) (-10.0861, 12.0659) (-9.8563, 11.8261) (-9.4717, 11.7311) (-9.1869, 11.7311) knots 0 0 0 1 2 3 4 4 4
  line L91 (-9.1869, 11.7311) -> (-7.7581, 11.7311)
  spline S94 degree 2 poles (-8.9321, 13.4147) (-8.6623, 13.4147) (-8.4875, 13.7545) (-8.4875, 14.1142) knots 0 0 0 1 2 2 2
  spline S95 degree 2 poles (-8.4875, 14.1142) (-8.4875, 14.4889) (-8.6623, 14.8336) (-8.9321, 14.8336) knots 0 0 0 1 2 2 2
  line L92 (-8.9321, 14.8336) -> (-9.6115, 14.8336)
  spline S96 degree 2 poles (-9.6115, 14.8336) (-9.8114, 14.8336) (-10.0512, 14.7037) (-10.1911, 14.3789) (-10.236, 13.8294) (-10.236, 13.4147) knots 0 0 0 1 2 3 4 4 4
  line L93 (-10.236, 13.4147) -> (-8.9321, 13.4147)
  spline S97 degree 2 poles (-4.1911, 15.4131) (-4.1211, 15.4131) (-4.1211, 15.3431) knots 0 0 0 1 1 1
  line L94 (-4.1211, 15.3431) -> (-4.1211, 14.8036)
  spline S98 degree 2 poles (-4.1211, 14.8036) (-4.1211, 14.7336) (-4.1911, 14.7336) knots 0 0 0 1 1 1
  line L95 (-4.1911, 14.7336) -> (-5.0254, 14.7336)
  spline S99 degree 2 poles (-5.0254, 14.7336) (-5.1802, 14.7336) (-5.405, 14.6887) (-5.5599, 14.5238) (-5.6349, 14.2091) (-5.6349, 13.9443) knots 0 0 0 1 2 3 4 4 4
  line L96 (-5.6349, 13.9443) -> (-5.6349, 11.1616)
  spline S100 degree 2 poles (-5.6349, 11.1616) (-5.6349, 11.0917) (-5.6948, 11.0917) knots 0 0 0 1 1 1
  line L97 (-5.6948, 11.0917) -> (-6.5691, 11.0917)
  spline S101 degree 2 poles (-6.5691, 11.0917) (-6.629, 11.0917) (-6.629, 11.1616) knots 0 0 0 1 1 1
  line L98 (-6.629, 11.1616) -> (-6.629, 13.9793)
  spline S102 degree 2 poles (-6.629, 13.9793) (-6.629, 14.4239) (-6.4292, 14.9884) (-6.0745, 15.2982) (-5.5949, 15.4131) (-5.3201, 15.4131) knots 0 0 0 1 2 3 4 4 4
  line L99 (-5.3201, 15.4131) -> (-4.1911, 15.4131)
  point P0 (0, 0)
  dimension "d0" = 58.5
  dimension "d1" = 28.5
  dimension "d2" = 2
  dimension "d3" = 21
  dimension "d4" = 18
  dimension "d5" = 2.2
  dimension "d6" = 2.2
  dimension "d7" = 10
  dimension "d8" = 3
  constraints: 2 other
extrude "돌출11" cut sketch "스케치11" against normal blind 1
